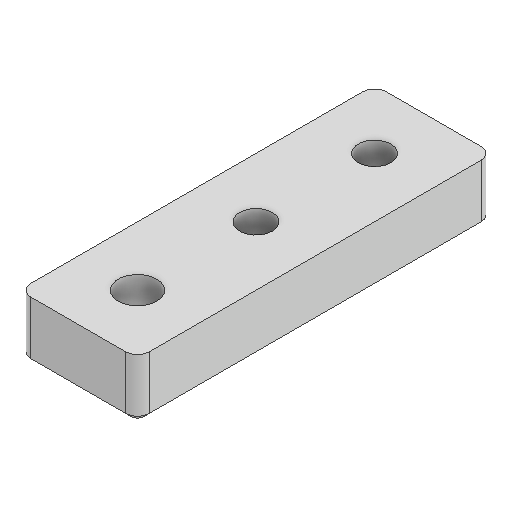
# Autodesk Inventor part: 3DP_PLA_Frame_Stiffener_and_Leg_REVB
Saved by Autodesk Inventor 2027 (Build 310192060, 192F)
## iProperties
Created: 2026-03-08
Part Number: 3DP_PLA_Frame_Stiffener_and_Leg_REVB
Material: Generic
Document SubType Name: Modeling
Designer: User
Density: 1 g/cm^3
Appearance: Default
Author: User
Autodesk Inventor part; units mm, degrees
ref_plane "YZ Plane" through (0, 0, 0) normal (1, 0, 0) x (0, 1, 0)
ref_plane "XZ Plane" through (0, 0, 0) normal (0, 1, 0) x (-1, 0, 0)
ref_plane "XY Plane" through (0, 0, 0) normal (0, 0, 1) x (1, 0, 0)
sketch "Sketch1" plane through (0, 0, 0) normal (0, 1, 0) x (-1, 0, 0)
  line L0 (10, 10) -> (-10, 10)
  line L1 (-10, 10) -> (-10, -10)
  line L2 (-10, -10) -> (10, -10)
  line L3 (10, -10) -> (10, 10)
  line L4 (-10, -10) -> (-10, -50)
  line L5 (-10, -50) -> (10, -50)
  line L6 (10, -50) -> (10, -10)
  point P0 (0, 0)
  point P1 (0, -20)
  point P2 (0, -40)
  dimension "d0" = 20
  dimension "d1" = 20
  dimension "d2" = 10
  dimension "d3" = 10
  dimension "d4" = 40
  dimension "d5" = 10
  dimension "d6" = 10
  constraints: 14 end point, 3 perpendicular, 2 parallel, 1 horizontal, 1 vertical
  measures "d0" distance of L2.end L1.end
  measures "d1" distance of L1.end L0.end
  measures "d2" distance from line of L3 point (0, 0)
  measures "d3" distance from line of L0 point (0, 0)
  measures "d4" distance of L1.end L4.end
  measures "d5" distance from line of point (0, -20) L2
  measures "d6" distance from line of L5 point (0, -40)
extrude "Extrusion1" add sketch "Sketch1" along normal blind 10
fillet "Fillet1" radius 2 4 edges at (10, 5, 10) (-10, 5, 10) (10, 5, -50) (-10, 5, -50)
hole "Hole1" at (0, 0, -20) at (0, 0, -40) direction (0, 1, 0) diameter 5.5 end through all
hole "Hole2" at (0, 0, 0) direction (0, 1, 0) diameter 6.5 end through all
hole "Hole3" at (0, 0, -40) at (0, 0, -20) direction (0, 1, 0) diameter 11 depth 5
hole "Hole4" at (0, 0, 0) direction (0, 1, 0) diameter 12 depth 5
chamfer "Chamfer1" distance 1 angle 45 8 edges at (-10, 0, -20) (-9.4142, 0, 9.4142) (0, 0, 10) (9.4142, 0, 9.4142) (10, 0, -20) (9.4142, 0, -49.4142) (0, 0, -50) (-9.4142, 0, -49.4142)
equation "\"d2\" = 0.5 * d0"
equation "\"d3\" = 0.5 * d1"
body "Solid1"
